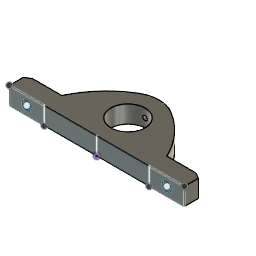
Pipe Mount (Autodesk Fusion 360 design; units mm, degrees)
Autodesk Fusion 360 part; units mm, degrees
sketch "Sketch1" plane through (0, 0, 0) normal (0, 0, 1) x (1, 0, 0)
  circle A0 centre (0, 0) radius 24.5
  circle A1 centre (0, 0) radius 44.5
  line L0 (0, -44.5) -> (125, -44.5)
  line L1 (0, -44.5) -> (-125, -44.5)
  line L2 (-37.1484, -24.5) -> (-125, -24.5)
  line L3 (37.1484, -24.5) -> (125, -24.5)
  line L4 (-125, -24.5) -> (-125, -44.5)
  line L5 (125, -24.5) -> (125, -44.5)
  line L6 (-125, -24.5) -> (-23.2758, 37.9274)
  line L7 (125, -24.5) -> (23.2758, 37.9274)
  arc A2 (-125, -24.5) -> (-34.5098, 28.0949) centre (-149.4066, 121.6341) ccw
  line L8 (0, 0) -> (0, 24.5)
  arc A3 (34.5098, 28.0949) -> (125, -24.5) centre (149.4066, 121.6341) ccw
  dimension "d1" = 49
  dimension "d2" = 20
  dimension "d3" = 125
  dimension "d4" = 125
  constraint coincident A0.centre A1.centre
  constraint coincident A1 L0.start
  constraint horizontal L0
  constraint parallel L0 L1
  constraint perpendicular L1 L4
  constraint perpendicular L0 L5
  constraint coincident A1 L6.end
  constraint tangent A1 L6
  constraint coincident A1 L7.end
  constraint tangent A1 L7
  constraint coincident A1 L2.start
  constraint coincident A1 L3.start
  constraint coincident A1 A2.end
  constraint tangent A1 A2
  constraint coincident A0 L8.end
  constraint vertical L8
  constraint symmetric L2.end L8 L3.end
  constraint symmetric A2.end L8 A3.start
  constraint symmetric A2 L8 A3
  measures "d1" diameter of A0
  measures "d3" distance of L0.start L0.end
  measures "d4" distance of L0.start L1.end
extrude "Extrude1" add sketch "Sketch1" along normal blind 25
sketch "Sketch2" plane through (0, -44.5, 0) normal (0, -1, 0) x (1, 0, 0)
  line L0 (-125, 0) -> (125, 0)
  line L1 (125, 0) -> (125, 25)
  line L2 (125, 25) -> (-125, 25)
  line L3 (-125, 25) -> (-125, 0)
  circle A0 centre (-100.0984, 12.5) radius 6.35
  line L4 (0, 0) -> (0, 25)
  circle A1 centre (100.0984, 12.5) radius 6.35
  line L5 (125, 25) -> (75, 25)
  line L6 (75, 25) -> (75, 0)
  line L7 (75, 0) -> (125, 0)
  line L8 (125, 0) -> (125, 25)
  line L9 (-125, 25) -> (-75, 25)
  line L10 (-75, 25) -> (-75, 0)
  line L11 (-75, 0) -> (-125, 0)
  line L12 (-125, 0) -> (-125, 25)
  dimension "d8" = 12.7
  dimension "d11" = 50
  dimension "d12" = 50
  constraint coincident L4.start origin
  constraint midpoint L2 L4.end
  constraint symmetric A0 L4 A1
  constraint horizontal L5
  constraint vertical L6
  constraint horizontal L7
  constraint vertical L8
  constraint coincident L0 L6.end
  constraint coincident L1.end L2.start
  constraint horizontal L9
  constraint vertical L10
  constraint horizontal L11
  constraint vertical L12
  constraint coincident L0 L10.end
  constraint coincident L2.end L3.start
  measures "d8" diameter of A0
  measures "d11" distance of L10.end L0.start
  measures "d12" distance of L6.end L0.end
extrude "Extrude2" cut sketch "Sketch2" against normal blind 130 contours A0 | A1
extrude "Extrude3" cut sketch "Sketch2" along normal blind 30 from surface at -55 contours L0 L2 L3 L9 L10 L11 L12 | L0 L1 L2 L5 L6 L7 L8
fillet "Fillet3" radius 132.5 2 edges at (75, 6.1846, 12.5) (-75, 6.1846, 12.5)
ref_plane "WorkPlane1" through (0, 44.5, 11.6623) normal (0, 1, 0) x (1, 0, 0)
sketch "Sketch3" plane through (0, 44.5, 0) normal (0, 1, 0) x (1, 0, 0)
  line L0 (0, 0) -> (0, -25) construction
  circle A0 centre (0, -12.5) radius 3.175
  dimension "d23" = 6.35
  constraint coincident L0.start origin
  constraint vertical L0
  constraint midpoint L0 A0.centre
  measures "d23" diameter of A0
extrude "Extrude4" cut sketch "Sketch3" against normal blind 40
